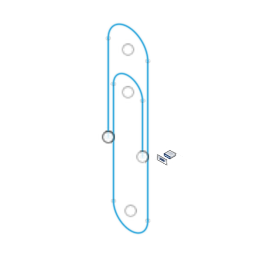
clip (Autodesk Fusion 360 design; units mm, degrees)
part number: 2026-08-26-10-02-50-047
Autodesk Fusion 360 part; units mm, degrees
sketch "Sketch1" plane through (0, 0, 0) normal (0, 0, 1) x (1, 0, 0)
sketch "Sketch2" plane through (0, 0, 0) normal (0, 0, 1) x (1, 0, 0)
sketch "Sketch3" plane through (0, 0, 0) normal (0, 0, 1) x (1, 0, 0)
  line L0 (-10, -5) -> (-10, 11.25)
  line L1 (-2.5, 11.25) -> (-2.5, -15)
  line L2 (-9, -15) -> (-9, 4.25)
  line L3 (-3.5, 4.25) -> (-3.5, -5)
  arc A0 (-2.5, 11.25) -> (-10, 11.25) centre (-6.25, 11.25) ccw
  arc A1 (-3.5, 4.25) -> (-9, 4.25) centre (-6.25, 4.25) ccw
  arc A2 (-9, -15) -> (-2.5, -15) centre (-5.75, -15) ccw
  dimension "d8" = 16.25
  dimension "d9" = 7.5
  dimension "d10" = 26.25
  dimension "d11" = 6.5
  dimension "d12" = 19.25
  dimension "d13" = 5.5
  dimension "d14" = 9.25
  constraint vertical L0
  constraint tangent L0 A0
  constraint tangent L2 A1
  constraint tangent L2 A2
  measures "d8" distance of L0.start L0.end
  measures "d9" distance of L0.end L1.start
  measures "d10" distance of L1.start L1.end
  measures "d11" distance of L1.end L2.start
  measures "d12" distance of L2.start L2.end
  measures "d13" distance of L2.end L3.start
  measures "d14" distance of L3.start L3.end
sketch "Sketch6" plane through (0, 0, 0) normal (0, 0, 1) x (1, 0, 0)
sketch "Sketch4" plane through (0, 0, 0) normal (0, 1, 0) x (1, 0, 0)
  circle A0 through (-9.625, 0, -5) (-10.1875, 0.3248, -5) (-10.1875, -0.3248, -5)
  dimension "d15" = 0.75
sketch "Sketch5" plane through (0, 0, 0) normal (0, 0, 1) x (1, 0, 0)
sketch "Sketch7" plane through (0, 0, 0) normal (0, 0, 1) x (1, 0, 0)
sketch "Sketch8" plane through (0, 0, 0) normal (0, 1, 0) x (1, 0, 0)
sweep "Sweep1" add profiles "Sketch4" path "Sketch3" along L0 A0 L1 A2 L2 A1 L3 section 1 contours A0 in plane through (0, -5, 0) normal (0, 1, 0)
sketch "Sketch9" plane through (0, -5, 0) normal (0, -1, 0) x (1, 0, 0)
  circle A0 centre (-3.5, 0) radius 0.375
